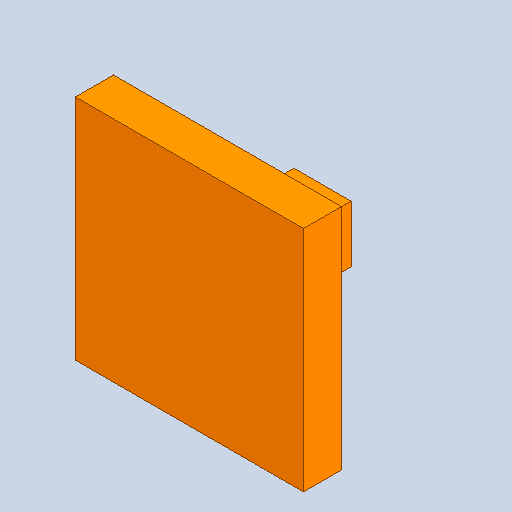
# Autodesk Inventor part: кнопка2часть
Saved by Autodesk Inventor 2024.2 (Build 282272000, 272)
## iProperties
Created: 2026-10-02
Part Number: кнопка2часть
Material: PA-CF
Document SubType Name: Modeling
Designer: katya_notebook
Density: 1.2 g/cm^3
Appearance: Типовые
Author: katya_notebook
Autodesk Inventor part; units mm, degrees
ref_plane "YZ Plane" through (0, 0, 0) normal (1, 0, 0) x (0, 1, 0)
ref_plane "XZ Plane" through (0, 0, 0) normal (0, 1, 0) x (-1, 0, 0)
sketch "Эскиз1" plane through (0, 0, 0) normal (0, 0, 1) x (1, 0, 0)
  line L0 (1.5, 1.5) -> (1.5, -1.5) projected
  line L1 (-1.5, 1.5) -> (1.5, 1.5) projected
  line L2 (-1.5, -1.5) -> (-1.5, 1.5) projected
  line L3 (1.5, -1.5) -> (-1.5, -1.5) projected
  line L4 (-1.5, -1.5) -> (1.5, -1.5)
  line L5 (1.5, -1.5) -> (1.5, 1.5)
  line L6 (1.5, 1.5) -> (-1.5, 1.5)
  line L7 (-1.5, 1.5) -> (-1.5, -1.5)
  line L8 (-1.5, -1.5) -> (1.5, 1.5) construction
  line L9 (1.5, -1.5) -> (-1.5, 1.5) construction
  point P0 (0, 0)
  constraints: 12 end point, 2 midpoint, 2 parallel, 1 horizontal, 1 perpendicular
ref_plane "РабПлоскость1" through (-1.5198, -1.5198, -5) normal (0, 0, 1) x (1, 0, 0)
extrude "Выдавливание1" add sketch "Эскиз1" against normal up to surface (5 mm away)
sketch "Эскиз2" plane through (0, 0, 0) normal (0, 0, 1) x (1, 0, 0)
  line L0 (6, -6) -> (-6, -6)
  line L1 (-6, -6) -> (-6, 6)
  line L2 (-6, 6) -> (6, 6)
  line L3 (6, 6) -> (6, -6)
  line L4 (6, -6) -> (-6, 6) construction
  line L5 (-6, -6) -> (6, 6) construction
  point P0 (0, 0)
  constraints: 12 end point, 2 midpoint, 2 parallel, 1 horizontal, 1 perpendicular, 1 other
extrude "Выдавливание2" add sketch "Эскиз2" along normal blind 2
